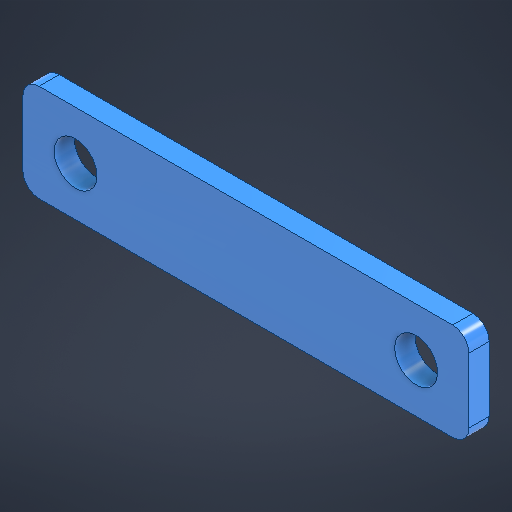
# Autodesk Inventor part: Bearing Spacer
Saved by Autodesk Inventor 2027.1 (Build 311270010, 270A)
## iProperties
Created: 2026-10-05
Part Number: Bearing Spacer
Material: Generic
Document SubType Name: Modeling
Designer: Ahmed
Density: 1 g/cm^3
Appearance: Cyan
Author: Ahmed
Autodesk Inventor part; units mm, degrees
ref_plane "YZ Plane" through (0, 0, 0) normal (1, 0, 0) x (0, 1, 0)
ref_plane "XZ Plane" through (0, 0, 0) normal (0, 1, 0) x (-1, 0, 0)
ref_plane "XY Plane" through (0, 0, 0) normal (0, 0, 1) x (1, 0, 0)
sketch "Sketch1" plane through (0, 0, 0) normal (0, 0, 1) x (1, 0, 0)
  line L0 (-25.5, 6) -> (25.5, 6)
  line L1 (27.5, 4) -> (27.5, -4)
  line L2 (25.5, -6) -> (-25.5, -6)
  line L3 (-27.5, -4) -> (-27.5, 4)
  line L4 (-27.5, 6) -> (27.5, -6) construction
  line L5 (27.5, 6) -> (-27.5, -6) construction
  line L6 (27.5, 0) -> (-27.5, 0)
  circle A0 centre (-21, 0) radius 2.65
  arc A1 (-25.5, 6) -> (-27.5, 4) centre (-25.5, 4) ccw
  arc A2 (-27.5, -4) -> (-25.5, -6) centre (-25.5, -4) ccw
  arc A3 (25.5, -6) -> (27.5, -4) centre (25.5, -4) ccw
  arc A4 (27.5, 4) -> (25.5, 6) centre (25.5, 4) ccw
  line L7 (0, -6) -> (0, 6)
  circle A5 centre (21, 0) radius 2.65
  point P0 (0, 0)
  dimension "d0" = 55
  dimension "d1" = 12
  dimension "d2" = 5.3
  dimension "d3" = 21
  dimension "d4" = 2
  constraints: 16 end point, 9 point on line, 8 point on circle, 8 tangent, 6 centre point, 6 midpoint, 3 equal radius, 2 parallel, 1 horizontal, 1 perpendicular, 1 symmetric about line, 1 other
  measures "d0" distance of L4.end L5.end
  measures "d1" distance of L5.start L4.end
  measures "d2" diameter of A0
  measures "d3" distance of point (0, 0) A0.centre
  measures "d4" radius of A1
extrude "Extrusion1" add sketch "Sketch1" along normal blind 2.5 contours L0 L7 L6 A0 L3 A1 | L0 A4 L1 L6 A5 L7 | L7 L2 A2 L3 L6 A0 | L6 A5 L1 A3 L2 L7
body "Solid1"
